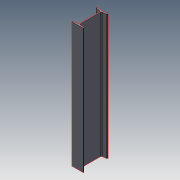
# Autodesk Inventor part: I-profil
Saved by Autodesk Inventor 2022.1 (Build 261234020, 234B)
## iProperties
Created: 2021-11-09
Part Number: I-profil
Checked By: Velcovsky
Material: S 235 JR / 1.0037
Description: =<profil>
Document SubType Name: Modeling
Designer: Velcovsky
Mass: 26243.6 g
Surface Area: 7154.48 cm^2
Volume: 3343.14 cm^3
Density: 7.85 g/cm^3
Appearance: Metall - Stahl
RuleStatus: InUse
BeforeDocSave0: profil
Author: Velcovsky
014_Norm: DIN 1025
velikost: 200
profil: I200 - l=1000
AIMD_WEIGHT01: 26,244 kg
AIMD_WEIGHT: 26.244
AIMD_WEIGHT_UNIT: kg
Autodesk Inventor part; units mm, degrees
ref_plane "YZ Plane" through (0, 0, 0) normal (1, 0, 0) x (0, 1, 0)
ref_plane "XZ Plane" through (0, 0, 0) normal (0, 1, 0) x (-1, 0, 0)
ref_plane "XY Plane" through (0, 0, 0) normal (0, 0, 1) x (1, 0, 0)
sketch "Náčrt2" plane through (0, 0, 0) normal (0, 0, 1) x (1, 0, 0)
  line L0 (-45, -100) -> (45, -100)
  line L1 (45, 100) -> (-45, 100)
  line L2 (0, -100) -> (0, 100) construction
  line L3 (-45, 0) -> (45, 0) construction
  line L4 (-45, 100) -> (-45, -100) construction
  line L5 (45, 100) -> (45, -100) construction
  line L6 (45, 100) -> (-45, -100) construction
  line L7 (-45, 100) -> (45, -100) construction
  line L8 (3.75, -79.9022) -> (-3.75, -79.9022) construction
  line L9 (-3.75, -79.9022) -> (-3.75, 79.9022)
  line L10 (-3.75, 79.9022) -> (3.75, 79.9022) construction
  line L11 (3.75, 79.9022) -> (3.75, -79.9022)
  line L12 (3.75, -79.9022) -> (-3.75, 79.9022) construction
  line L13 (-3.75, -79.9022) -> (3.75, 79.9022) construction
  line L14 (-45, 100) -> (-45, 95.764)
  line L15 (45, 100) -> (45, 95.764)
  line L16 (-45, -100) -> (-45, -95.764)
  line L17 (45, -100) -> (45, -95.764)
  arc A0 (-41.1239, -91.3075) -> (-45, -95.764) centre (-40.5, -95.764) ccw
  line L18 (-41.1239, -91.3075) -> (-10.2018, -86.9782)
  arc A1 (-10.2018, -86.9782) -> (-3.75, -79.9022) centre (-11.2418, -79.5506) ccw
  line L19 (10.2018, 86.9782) -> (-10.2018, 86.9782) construction
  line L20 (-10.2018, 86.9782) -> (-10.2018, -86.9782) construction
  line L21 (-10.2018, -86.9782) -> (10.2018, -86.9782) construction
  line L22 (10.2018, -86.9782) -> (10.2018, 86.9782) construction
  line L23 (10.2018, 86.9782) -> (-10.2018, -86.9782) construction
  line L24 (-10.2018, 86.9782) -> (10.2018, -86.9782) construction
  line L25 (41.1239, 91.3075) -> (-41.1239, 91.3075) construction
  line L26 (-41.1239, 91.3075) -> (-41.1239, -91.3075) construction
  line L27 (-41.1239, -91.3075) -> (41.1239, -91.3075) construction
  line L28 (41.1239, -91.3075) -> (41.1239, 91.3075) construction
  line L29 (41.1239, 91.3075) -> (-41.1239, -91.3075) construction
  line L30 (-41.1239, 91.3075) -> (41.1239, -91.3075) construction
  arc A2 (3.75, -79.9022) -> (10.2018, -86.9782) centre (11.2418, -79.5506) ccw
  arc A3 (45, -95.764) -> (41.1239, -91.3075) centre (40.5, -95.764) ccw
  line L31 (10.2018, -86.9782) -> (41.1239, -91.3075)
  arc A4 (-3.75, 79.9022) -> (-10.2018, 86.9782) centre (-11.2418, 79.5506) ccw
  line L32 (-41.1239, 91.3075) -> (-10.2018, 86.9782)
  arc A5 (-45, 95.764) -> (-41.1239, 91.3075) centre (-40.5, 95.764) ccw
  arc A6 (10.2018, 86.9782) -> (3.75, 79.9022) centre (11.2418, 79.5506) ccw
  line L33 (10.2018, 86.9782) -> (41.1239, 91.3075)
  arc A7 (41.1239, 91.3075) -> (45, 95.764) centre (40.5, 95.764) ccw
  point P0 (0, 0)
  point P1 (-22.5, -88.7)
  dimension "hv" = 200
  dimension "b" = 90
  dimension "t2" = 11.3
  dimension "t1" = 7.5
  dimension "r1" = 4.5
  dimension "r" = 7.5
  dimension "uhel" = 7.97
  dimension "d51" = 22.5
  constraints: 68 end point, 16 point on circle, 14 midpoint, 10 tangent, 8 centre point, 6 horizontal, 6 parallel, 5 point on line, 3 equal length, 3 perpendicular, 2 vertical
  measures "hv" vertical distance of L0.end L1.end
  measures "b" distance of L1.start L1.end
  measures "t2" distance from line of L0 point (-22.5, -88.7)
  measures "t1" distance between parallel lines of L11 L9
  measures "r1" radius of A0
  measures "r" radius of A1
  measures "uhel" angle of L0 L18
  measures "d51" distance from line of point (-22.5, -88.7) L4
extrude "Vysunutí1" add sketch "Náčrt2" along normal blind 1000
equation "\"G_L\" = delka"
equation "\"delka\" = 1000"
